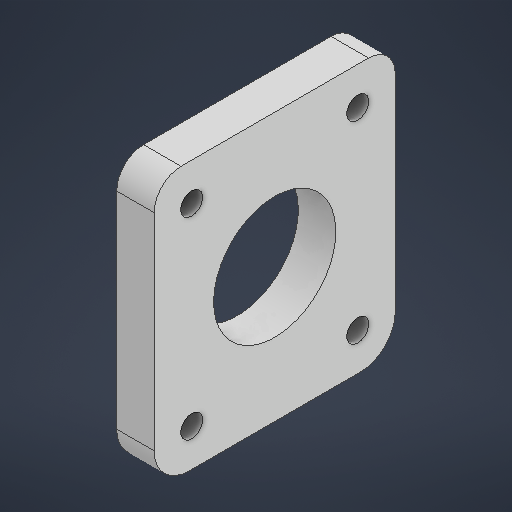
# Autodesk Inventor part: plate_arm_braing_
Saved by Autodesk Inventor 2027.1 (Build 311270010, 270A)
## iProperties
Created: 2026-10-10
Part Number: plate_arm_braing_
Material: Generic
Document SubType Name: Modeling
Designer: lucao
Density: 0.478884 g/cm^3
Appearance: Default
Mass: 5.9 g
Surface Area: 56.4304 cm^2
Volume: 12.3203 cm^3
Author: lucao
## iProperties of the stored document plate_arm_bearing_fix_3DPrint.ipt
Created: 2026-10-13
Part Number: plate_arm_bearing_fix_3DPrint
Material: Generic
Document SubType Name: Modeling
Designer: lucao
Density: 1 g/cm^3
Appearance: Default
Author: lucao
Autodesk Inventor part; units mm, degrees
ref_plane "YZ Plane" through (0, 0, 0) normal (1, 0, 0) x (0, 1, 0)
ref_plane "XZ Plane" through (0, 0, 0) normal (0, 1, 0) x (-1, 0, 0)
ref_plane "XY Plane" through (0, 0, 0) normal (0, 0, 1) x (1, 0, 0)
sketch "Sketch1" plane through (0, 0, 0) normal (1, 0, 0) x (0, 1, 0)
  line L0 (-25, 22.5) -> (25, 22.5)
  line L1 (25, 22.5) -> (25, -22.5)
  line L2 (25, -22.5) -> (-25, -22.5)
  line L3 (-25, -22.5) -> (-25, 22.5)
  line L4 (-25, 22.5) -> (25, -22.5) construction
  line L5 (25, 22.5) -> (-25, -22.5) construction
  circle A0 centre (18, 15.5) radius 2.05
  circle A1 centre (18, -15.5) radius 2.05
  circle A2 centre (-18, -15.5) radius 2.05
  circle A3 centre (-18, 15.5) radius 2.05
  circle A4 centre (0, 0) radius 11.4
  dimension "d0" = 50
  dimension "d1" = 45
  dimension "d2" = 4.1
  dimension "d3" = 4.1
  dimension "d4" = 4.1
  dimension "d5" = 4.1
  dimension "d6" = 7
  dimension "d7" = 7
  dimension "d8" = 7
  dimension "d9" = 7
  dimension "d13" = 22.8
  constraints: 12 end point, 5 centre point, 2 horizontal alignment, 2 midpoint, 2 parallel, 2 vertical alignment, 1 coincident, 1 horizontal, 1 perpendicular
  measures "d0" distance of L1.end L2.end
  measures "d1" distance of L0.end L1.end
  measures "d2" diameter of A0
  measures "d3" diameter of A1
  measures "d4" diameter of A2
  measures "d5" diameter of A3
  measures "d6" distance from line of L1 A0.centre
  measures "d7" distance from line of L0 A0.centre
  measures "d8" distance from line of L3 A3.centre
  measures "d9" distance from line of L2 A1.centre
  measures "d13" diameter of A4
extrude "Extrusion1" add sketch "Sketch1" along normal blind 7
fillet "Fillet1" radius 6.5 2 edges at (3.5, -25, 22.5) (3.5, -25, -22.5)
fillet "Fillet2" radius 5 2 edges at (3.5, 25, -22.5) (3.5, 25, 22.5)
body "Solid1"
